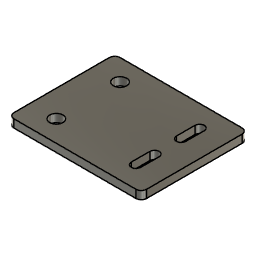
SMPS_support-1_2025-02-11 (Autodesk Fusion 360 design; units mm, degrees)
Autodesk Fusion 360 part; units mm, degrees
sketch "스케치1" plane through (0, 0, 0) normal (0, 0, 1) x (1, 0, 0)
  line L0 (0, 0) -> (50, 0)
  line L1 (0, 40) -> (0, 0)
  line L2 (50, 40) -> (50, 0)
  line L3 (0, 40) -> (50, 40)
  circle A0 centre (10, 32) radius 1.75
  circle A1 centre (10, 8) radius 1.75
  line L4 (38.25, 32) -> (38.25, 25)
  line L5 (38.25, 15) -> (38.25, 8)
  line L6 (41.75, 32) -> (41.75, 24.9986)
  line L7 (41.75, 15.0014) -> (41.75, 8)
  arc A2 (41.75, 32) -> (38.25, 32) centre (40, 32) ccw
  arc A3 (38.25, 25) -> (41.75, 25.0014) centre (40, 25) ccw
  arc A4 (41.75, 14.9986) -> (38.25, 15) centre (40, 15) ccw
  arc A5 (38.25, 8) -> (41.75, 8) centre (40, 8) ccw
  dimension "d3" = 3.5
  dimension "d4" = 3.5
  constraint horizontal L0
  constraint perpendicular L0 L1
  constraint horizontal L3
  constraint coincident L0 L1.end
  constraint coincident L1 L0.start
  constraint tangent L6 A5
  constraint tangent L4 A5
  constraint collinear L4 L5
  constraint coincident L6.end A3
  constraint coincident L7.start A4
  constraint collinear L6 L7
  constraint coincident L6 A3.end
  constraint coincident L7 A4.start
  measures "d3" diameter of A0
  measures "d4" diameter of A1
extrude "돌출1" add sketch "스케치1" along normal blind 3
fillet "필렛1" radius 2 3 edges at (50, 0, 1.5) (50, 40, 1.5) (0, 0, 1.5)
fillet "필렛2" radius 2 1 edges at (0, 40, 1.5)
sketch "스케치2" plane through (0, 0, 3) normal (0, 0, 1) x (-1, 0, 0)
  arc A0 (-2, -40) -> (0, -38) centre (-2, -38) ccw
  line L0 (0, -38) -> (0, -2)
  arc A1 (0, -2) -> (-2, 0) centre (-2, -2) ccw
  line L1 (-2, 0) -> (-48, 0)
  arc A2 (-48, 0) -> (-50, -2) centre (-48, -2) ccw
  line L2 (-50, -2) -> (-50, -38)
  arc A3 (-50, -38) -> (-48, -40) centre (-48, -38) ccw
  line L3 (-48, -40) -> (-2, -40)
  arc A4 (-41.75, -14.9986) -> (-38.25, -15) centre (-40, -15) ccw
  line L4 (-41.75, -14.9986) -> (-41.75, -8)
  arc A5 (-38.25, -8) -> (-41.75, -8) centre (-40, -8) ccw
  line L5 (-38.25, -8) -> (-38.25, -15)
  circle A6 centre (-10, -8) radius 1.75
  circle A7 centre (-10, -32) radius 1.75
  arc A8 (-41.75, -32) -> (-38.25, -32) centre (-40, -32) ccw
  line L6 (-41.75, -32) -> (-41.75, -25.0014)
  arc A9 (-38.25, -25) -> (-41.75, -25.0014) centre (-40, -25) ccw
  line L7 (-38.25, -25) -> (-38.25, -32)
  circle A10 centre (-10, -32) radius 2.5
  circle A11 centre (-10, -8) radius 2.5
  dimension "d13" = 5
  dimension "d14" = 5
  constraint concentric A7 A10
  constraint concentric A6 A11
  measures "d13" diameter of A10
  measures "d14" diameter of A11
extrude "돌출2" cut sketch "스케치2" against normal blind 3 contours A10 | A11
